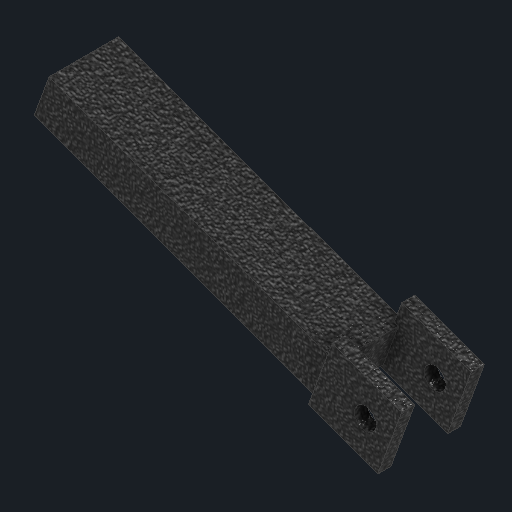
# Autodesk Inventor part: tripod_brace_arm
Saved by Autodesk Inventor 2027.1 (Build 311270010, 270A)
## iProperties
Created: 2026-11-04
Part Number: tripod_brace_arm
Material: Generic
Description: Tray brace arm (leg to centre hub), horizontal
Document SubType Name: Modeling
Designer: Claude (from photos)
Density: 1 g/cm^3
Appearance: Black Cast
Author: alexg
Autodesk Inventor part; units mm, degrees
sketch "Arm sketch" plane through (0, 0, 0) normal (0, 0, 1) x (1, 0, 0)
  line L0 (-118.1248, -178.3551) -> (-52.3463, -202.2965)
  line L1 (-52.3463, -202.2965) -> (-48.9261, -192.8995)
  line L2 (-48.9261, -192.8995) -> (-114.7046, -168.9581)
  line L3 (-114.7046, -168.9581) -> (-118.1248, -178.3551)
  constraints: 8 end point
extrude "Arm" add sketch "Arm sketch" along normal mid plane 16
ref_plane "Work Plane1" through (0, 0, 6.5) normal (0, 0, 1) x (1, 0, 0)
sketch "Fork cheek +z sketch" plane through (0, 0, 6.5) normal (0, 0, 1) x (1, 0, 0)
  line L0 (-53.6281, -202.8941) -> (-37.6533, -208.7085)
  line L1 (-37.6533, -208.7085) -> (-32.181, -193.6734)
  line L2 (-32.181, -193.6734) -> (-48.1557, -187.8591)
  line L3 (-48.1557, -187.8591) -> (-53.6281, -202.8941)
  constraints: 8 end point
extrude "Fork cheek +z" add sketch "Fork cheek +z sketch" along normal blind 3
ref_plane "Work Plane2" through (0, 0, -6.5) normal (0, 0, 1) x (1, 0, 0)
sketch "Fork cheek -z sketch" plane through (0, 0, -6.5) normal (0, 0, 1) x (1, 0, 0)
  line L0 (-53.6281, -202.8941) -> (-37.6533, -208.7085)
  line L1 (-37.6533, -208.7085) -> (-32.181, -193.6734)
  line L2 (-32.181, -193.6734) -> (-48.1557, -187.8591)
  line L3 (-48.1557, -187.8591) -> (-53.6281, -202.8941)
  constraints: 8 end point
extrude "Fork cheek -z" add sketch "Fork cheek -z sketch" against normal blind 3
ref_plane "Work Plane3" through (0, 0, -12) normal (0, 0, 1) x (1, 0, 0)
sketch "Pin hole sketch" plane through (0, 0, -12) normal (0, 0, 1) x (1, 0, 0)
  circle A0 centre (-40.5553, -199.1388) radius 2.5
  constraints: 1 centre point
extrude "Pin hole" cut sketch "Pin hole sketch" along normal blind 24
body "Solid1"
